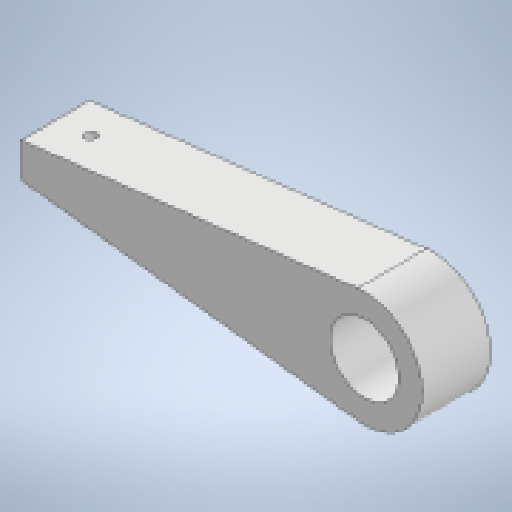
# Autodesk Inventor part: seguidor3
Saved by Autodesk Inventor 2025.2 (Build 292293000, 293)
## iProperties
Created: 2025-05-17
Part Number: seguidor3
Material: Generic
Document SubType Name: Modeling
Designer: laura
Density: 1 g/cm^3
Appearance: Default
Author: laura
Autodesk Inventor part; units mm, degrees
ref_plane "YZ Plane" through (0, 0, 0) normal (1, 0, 0) x (0, 1, 0)
ref_plane "XZ Plane" through (0, 0, 0) normal (0, 1, 0) x (-1, 0, 0)
ref_plane "XY Plane" through (0, 0, 0) normal (0, 0, 1) x (1, 0, 0)
sketch "Sketch1" plane through (0, 0, 0) normal (0, 0, 1) x (1, 0, 0)
  circle A0 centre (0, 0) radius 3
  line L0 (-0.5951, 5) -> (-30, 1.5)
  line L1 (-30, -1.5) -> (-0.5951, -5)
  arc A1 (-0.5951, -5) -> (-0.5951, 5) centre (0, 0) ccw
  line L2 (0, 0) -> (-30, 0) construction
  line L3 (-30, -1.5) -> (-30, 1.5)
  dimension "d0" = 6
  dimension "d2" = 10
  dimension "d4" = 30
  dimension "d11" = 3
  constraints: 8 end point, 2 centre point, 2 coincident, 2 point on circle, 2 tangent, 1 horizontal, 1 midpoint, 1 vertical
  measures "d0" diameter of A0
  measures "d2" distance of L0.start L1.end
  measures "d4" distance of L2.end L2.start
  measures "d11" distance of L1.start L0.end
extrude "Extrusion1" add sketch "Sketch1" against normal blind 6
sketch "Sketch2" plane through (-30, -1.5, -6) normal (-0.1182, -0.993, 0) x (0.993, -0.1182, 0)
  line L0 (2.6454, 6) -> (2.6454, 0) construction
  line L1 (-0.3546, 0) -> (28.4305, 0) construction
  line L2 (-0.3546, 6) -> (-0.3546, 0) construction
  line L3 (-0.3546, 3) -> (2.6454, 3) construction
  line L4 (0, 6) -> (29.6124, 6) construction
  circle A0 centre (2.6454, 3) radius 0.5
  dimension "d7" = 3
  dimension "d8" = 1
  constraints: 4 end point, 2 midpoint, 2 point on line, 1 centre point, 1 coincident, 1 vertical
  measures "d7" distance between parallel lines of L2 L0
  measures "d8" diameter of A0
extrude "Extrusion2" cut sketch "Sketch2" against normal through all
body "Solid1"
